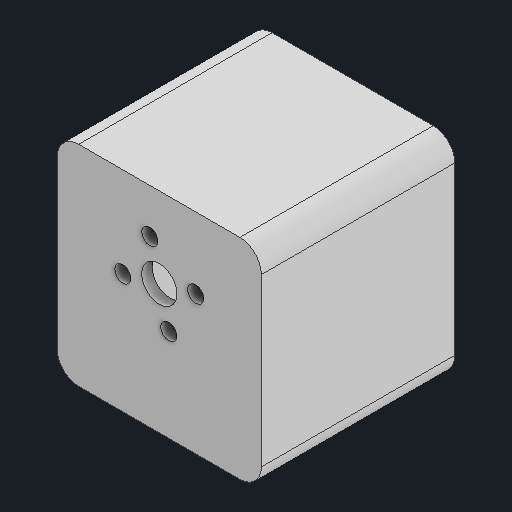
# Autodesk Inventor part: cajita
Saved by Autodesk Inventor 2027.2 (Build 312334000, 334)
## iProperties
Created: 2026-09-18
Part Number: cajita
Material: Genérico
Document SubType Name: Modeling
Designer: alexa
Density: 1 g/cm^3
Appearance: Valor por defecto
Project: Star tracker
Mass: 11.7818 g
Surface Area: 125.577 cm^2
Volume: 11.7818 cm^3
Author: alexa
Title: Porta camara
Autodesk Inventor part; units mm, degrees
ref_plane "YZ Plane" through (0, 0, 0) normal (1, 0, 0) x (0, 1, 0)
ref_plane "XZ Plane" through (0, 0, 0) normal (0, 1, 0) x (-1, 0, 0)
ref_plane "XY Plane" through (0, 0, 0) normal (0, 0, 1) x (1, 0, 0)
sketch "Boceto1" plane through (0, 0, 0) normal (0, 0, 1) x (1, 0, 0)
  line L0 (17, 17.5) -> (17, -17.5) projected
  line L1 (-17, 17.5) -> (17, 17.5) projected
  line L2 (-17, -17.5) -> (-17, 17.5) projected
  line L3 (17, -17.5) -> (-17, -17.5) projected
  circle A0 centre (14.5, 15) radius 1.5 projected
  circle A1 centre (14.5, -15) radius 1.5 projected
  circle A2 centre (-14.5, -15) radius 1.5 projected
  circle A3 centre (-14.5, 15) radius 1.5 projected
  circle A4 centre (7.62, -9.69) radius 0.5 projected
  circle A5 centre (5.08, -12.23) radius 0.5 projected
  circle A6 centre (5.08, -9.69) radius 0.5 projected
  circle A7 centre (2.54, -12.23) radius 0.5 projected
  circle A8 centre (2.54, -9.69) radius 0.5 projected
  circle A9 centre (10, 4.5) radius 0.9 projected
  circle A10 centre (10.16, -12.23) radius 0.5 projected
  circle A11 centre (10.16, -9.69) radius 0.5 projected
  circle A12 centre (7.62, -12.23) radius 0.5 projected
  circle A13 centre (-5.08, -9.69) radius 0.5 projected
  circle A14 centre (-7.62, -12.23) radius 0.5 projected
  circle A15 centre (-7.62, -9.69) radius 0.5 projected
  circle A16 centre (-10.16, -12.23) radius 0.5 projected
  circle A17 centre (-10.16, -9.69) radius 0.5 projected
  circle A18 centre (-2.54, -12.23) radius 0.5 projected
  circle A19 centre (-2.54, -9.69) radius 0.5 projected
  circle A20 centre (-5.08, -12.23) radius 0.5 projected
  circle A21 centre (0, -9.69) radius 0.5 projected
  circle A22 centre (0, -12.23) radius 0.5 projected
  circle A23 centre (-10, 4.5) radius 0.9 projected
  line L4 (19, 19.5) -> (19, -19.5)
  line L5 (19, -19.5) -> (-19, -19.5)
  line L6 (-19, -19.5) -> (-19, 19.5)
  line L7 (-19, 19.5) -> (19, 19.5)
  circle A24 centre (-14.5, 15) radius 2.5
  circle A25 centre (14.5, 15) radius 2.5
  circle A26 centre (14.5, -15) radius 2.5
  circle A27 centre (-14.5, -15) radius 2.5
  line L8 (14.5, 12.5) -> (17, 12.5)
  line L9 (14.5, -12.5) -> (17, -12.5)
  line L10 (12, -15) -> (12, -17.5)
  line L11 (12, 15) -> (12, 17.5)
  line L12 (-12, 15) -> (-12, 17.5)
  line L13 (-14.5, 12.5) -> (-17, 12.5)
  line L14 (-14.5, -12.5) -> (-17, -12.5)
  line L15 (-12, -15) -> (-12, -17.5)
  point P0 (0, 0)
  dimension "d0" = 2
  constraints: 24 end point, 11 tangent, 10 point on line, 8 point on circle, 5 perpendicular, 4 centre point, 4 coincident, 1 horizontal, 1 parallel, 3 other
  measures "d0" distance between parallel lines of L1 L7
extrude "Extrusión1" add sketch "Boceto1" along normal blind 5 contours L0 A25 L1 | L0 L8 A25 | A25 | A25 L11 L1 | L0 A26 L9 | L12 A24 L1 | A26 | L0 L3 A26 | A24 L2 L1 | A24 | L3 L10 A26 | A24 L13 L2 | L3 A27 L15 | L14 A27 L2 | L3 L2 A27 | A27 | L4 L5 L6 L7
extrude "Extrusión2" add sketch "Boceto1" along normal blind 36 contours L4 L5 L6 L7
sketch "Boceto2" plane through (0, 0, 36) normal (0, 0, 1) x (1, 0, 0)
  line L0 (-19, 19.5) -> (-19, -19.5) projected
  line L1 (-19, -19.5) -> (19, -19.5) projected
  line L2 (19, -19.5) -> (19, 19.5) projected
  line L3 (19, 19.5) -> (-19, 19.5) projected
  line L4 (17, -17.5) -> (-17, -17.5) projected
  line L5 (-17, -17.5) -> (-17, 17.5) projected
  line L6 (-17, 17.5) -> (17, 17.5) projected
  line L7 (17, 17.5) -> (17, -17.5) projected
  circle A0 centre (0, 4.5) radius 10
  circle A1 centre (1.7663, -2.2735) radius 1.5
  circle A2 centre (6.7735, 6.2663) radius 1.5
  circle A3 centre (-1.7663, 11.2735) radius 1.5
  circle A4 centre (-6.7735, 2.7337) radius 1.5
  circle A5 centre (0, 4.5) radius 1.75
  point P0 (0, 0)
  constraints: 6 centre point
extrude "Extrusión3" add sketch "Boceto2" against normal blind 2 contours L4 L5 L6 L7 | A0 | A5
sketch "Boceto3" plane through (-19, -19.5, 0) normal (0, -1, 0) x (1, 0, 0)
  line L0 (0, 0) -> (38, 0) projected
  line L1 (38, 0) -> (38, 36) projected
  line L2 (0, 36) -> (38, 36) projected
  line L3 (0, 0) -> (0, 36) projected
  line L4 (7.57, 0) -> (7.57, 2.5) projected
  line L5 (30.43, 2.5) -> (30.43, 0) projected
  line L6 (7.57, 2.5) -> (7.57, 36)
  line L7 (30.43, 2.5) -> (30.43, 36)
  line L8 (7.57, 36) -> (7.57, 16)
  line L9 (7.57, 16) -> (30.43, 16)
  line L10 (7.57, 36) -> (7.57, 34)
  line L11 (7.57, 34) -> (30.6195, 34)
  point P0 (19, 0)
  point P1 (30.43, 34)
  dimension "d7" = 20
  dimension "d8" = 2
  constraints: 12 end point, 5 point on line, 3 perpendicular, 1 parallel
  measures "d7" distance of L6.end L8.end
  measures "d8" distance of L6.end L10.end
extrude "Extrusión4" cut sketch "Boceto3" against normal blind 2 contours L6 L11 L7 L9
fillet "Empalme1" radius 4 4 edges at (19, -19.5, 18) (-19, -19.5, 18) (-19, 19.5, 18) (19, 19.5, 18)
sketch "Boceto4" plane through (0, 0, 34) normal (0, 0, -1) x (-1, 0, 0)
  circle A0 centre (0, 4.5) radius 3.292
  point P0 (0, 0)
  constraints: 1 centre point
extrude "Extrusión5" cut sketch "Boceto4" against normal blind 2
